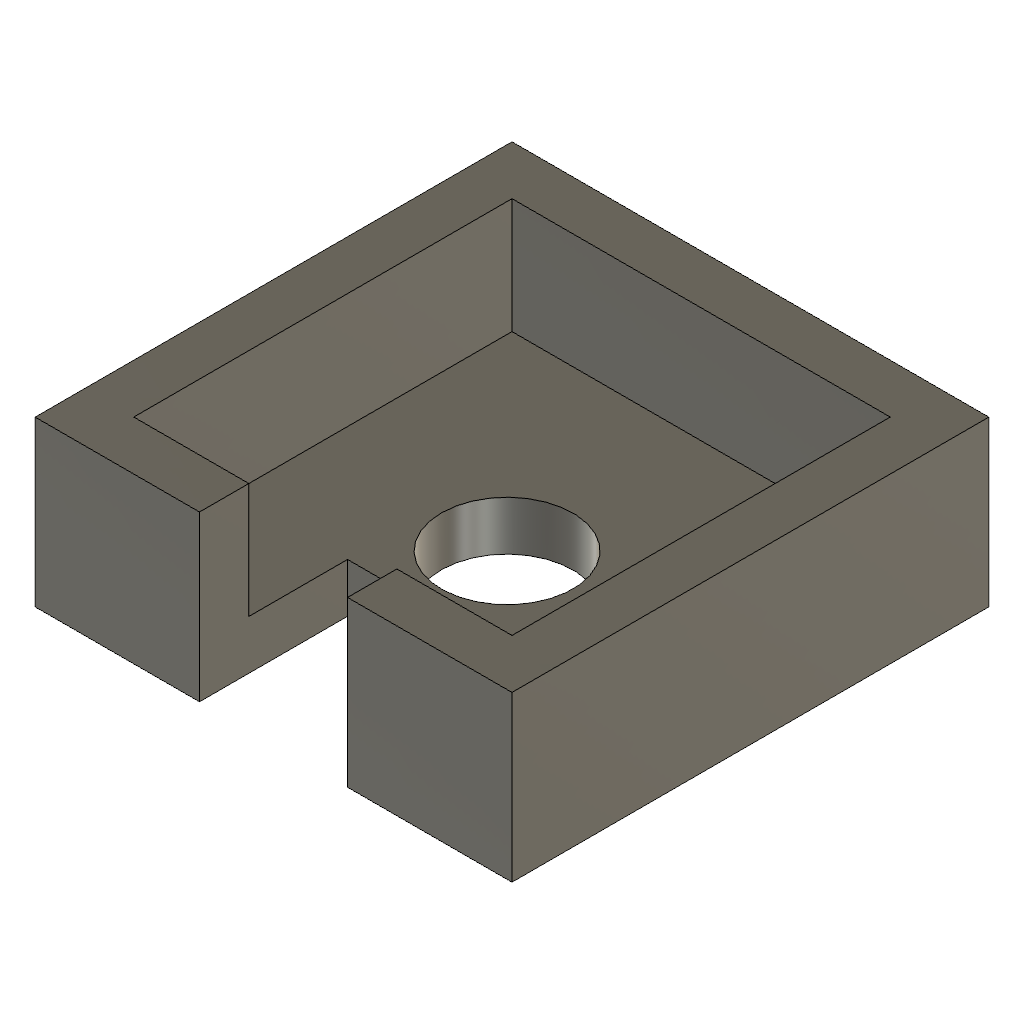
Solanoid Cap (Autodesk Fusion 360 design; units mm, degrees)
Autodesk Fusion 360 part; units mm, degrees
sketch "Sketch1" plane through (0, 0, 0) normal (0, 0, 1) x (1, 0, 0)
  line L0 (11.6, 11.7) -> (-11.4, 11.7)
  line L1 (-11.4, 11.7) -> (-11.4, -11.3)
  line L2 (-11.4, -11.3) -> (11.6, -11.3)
  line L3 (11.6, -11.3) -> (11.6, 11.7)
  line L4 (-14.4, -14.3) -> (14.6, -14.3)
  line L5 (14.6, -14.3) -> (14.6, 14.7)
  line L6 (14.6, 14.7) -> (-14.4, 14.7)
  line L7 (-14.4, 14.7) -> (-14.4, -14.3)
  circle A0 centre (0, 0) radius 4
  line L8 (4.6, -8.3) -> (-4.4, -8.3)
  line L9 (-4.4, -8.3) -> (-4.4, -14.3)
  line L10 (-4.4, -14.3) -> (4.6, -14.3)
  line L11 (4.6, -14.3) -> (4.6, -8.3)
  line L12 (4.6, -8.3) -> (-4.4, -14.3) construction
  line L13 (-4.4, -8.3) -> (4.6, -14.3) construction
  line L14 (-4.4, -8.3) -> (4.6, -8.3)
  line L15 (4.6, -8.3) -> (4.6, -5.3)
  line L16 (4.6, -5.3) -> (-4.4, -5.3)
  line L17 (-4.4, -5.3) -> (-4.4, -8.3)
  point P0 (0.1, -11.3)
  dimension "d1" = 23
  dimension "d2" = 23
  dimension "d3" = 3
  dimension "d4" = 9
  dimension "d5" = 6
  dimension "d10" = 8
  dimension "d12" = 11.3
  dimension "d13" = 11.6
  dimension "d14" = 9
  dimension "d15" = 3
  constraint horizontal L0
  constraint perpendicular L0 L1
  constraint parallel L0 L2
  constraint parallel L1 L3
  constraint coincident A0.centre origin
  constraint horizontal L8
  constraint perpendicular L8 L9
  constraint parallel L8 L10
  constraint parallel L9 L11
  constraint coincident L12 P0
  constraint coincident L13 P0
  constraint midpoint L2 P0
  constraint horizontal L14
  constraint vertical L15
  constraint horizontal L16
  constraint vertical L17
  measures "d1" distance of L1.end L2.end
  measures "d2" distance of L0.end L1.end
  measures "d4" distance of L9.end L10.end
  measures "d5" distance of L8.end L9.end
  measures "d10" diameter of A0
  measures "d12" distance of A0.centre L2
  measures "d13" distance of L3 A0.centre
  measures "d14" distance of L8.end L8.start
  measures "d15" distance of L8.end L16.end
extrude "Extrude1" add sketch "Sketch1" along normal blind 3 contours L0 L1 L2 L3 L9 L11 L15 L16 L17 | L8 L14 L15 L16 L17
extrude "Extrude2" add sketch "Sketch1" along normal blind 10 contours L0 L1 L2 L3 L4 L5 L6 L7 L9 L11
extrude "Extrude3" cut sketch "Sketch1" along normal blind 16 contours L8 L14 L15 L16 L17
